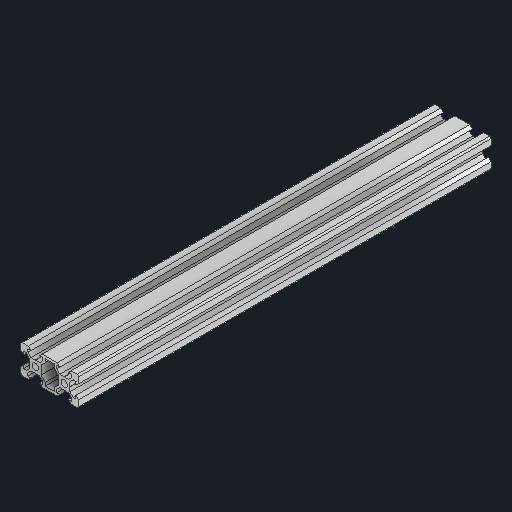
# Autodesk Inventor part: Perfil Estrutural em Alumínio 20x40 V-Slot - Canal 6 (286mm)
Saved by Autodesk Inventor 2026.1 (Build 301233000, 233)
## iProperties
Created: 2025-08-09
Part Number: Perfil Estrutural em Alumínio 20x40 V-Slot - Canal 6 (286mm)
Material: Alumínio 6061
Document SubType Name: Modeling
Designer: Cliente
Mass: 375 g
Surface Area: 849.316 cm^2
Volume: 84.4024 cm^3
Density: 2.5414 g/cm^3
Appearance: Alumínio - Polido
Author: Cliente
Autodesk Inventor part; units mm, degrees
ref_plane "YZ Plane" through (0, 0, 0) normal (1, 0, 0) x (0, 1, 0)
ref_plane "XZ Plane" through (0, 0, 0) normal (0, 1, 0) x (-1, 0, 0)
ref_plane "XY Plane" through (0, 0, 0) normal (0, 0, 1) x (1, 0, 0)
sketch "Esboço1" plane through (0, 0, 0) normal (0, 0, 1) x (1, 0, 0)
  line L0 (0, -10) -> (-19, -10)
  line L1 (-20, -9) -> (-20, 9)
  line L2 (-19, 10) -> (0, 10)
  line L3 (0, 10) -> (0, -10)
  line L4 (0, -10) -> (-20, 10) construction
  line L5 (-20, -10) -> (0, 10) construction
  circle A0 centre (-10, 0) radius 2.3
  line L6 (-6, -4) -> (-14, -4)
  line L7 (-14, -4) -> (-14, 4)
  line L8 (-14, 4) -> (-6, 4)
  line L9 (-6, 4) -> (-6, -4)
  line L10 (-6, -4) -> (-14, 4) construction
  line L11 (-14, -4) -> (-6, 4) construction
  line L12 (-13, 8.2) -> (-7, 8.2)
  line L13 (-13, 8.2) -> (-14.8, 10)
  line L14 (-13, 8.2) -> (-10.4544, 8.2) construction
  line L15 (-7, 8.2) -> (-5.2, 10)
  line L16 (-13, 4) -> (-7, 4)
  line L17 (-15.2, 8.2) -> (-15.2, 6.2)
  line L18 (-13, 4) -> (-15.2, 6.2)
  line L19 (-13, 4) -> (-9.8887, 4) construction
  line L20 (-13, 8.2) -> (-15.2, 8.2)
  line L21 (-7, 4) -> (-4.8, 6.2)
  line L22 (-4.8, 6.2) -> (-4.8, 8.2)
  line L23 (-4.8, 8.2) -> (-7, 8.2)
  line L24 (-18.2, -3) -> (-20, -4.8)
  line L25 (-18.2, -5.2) -> (-16.2, -5.2)
  line L26 (-18.2, -3) -> (-18.2, -5.2)
  line L27 (-18.2, 5.2) -> (-18.2, 3)
  line L28 (-18.2, 3) -> (-20, 4.8)
  line L29 (-14, -3) -> (-16.2, -5.2)
  line L30 (-14, 3) -> (-16.2, 5.2)
  line L31 (-16.2, 5.2) -> (-18.2, 5.2)
  line L32 (-7, -8.2) -> (-5.2, -10)
  line L33 (-4.8, -8.2) -> (-4.8, -6.2)
  line L34 (-7, -8.2) -> (-4.8, -8.2)
  line L35 (-15.2, -8.2) -> (-13, -8.2)
  line L36 (-13, -8.2) -> (-14.8, -10)
  line L37 (-7, -4) -> (-4.8, -6.2)
  line L38 (-13, -4) -> (-15.2, -6.2)
  line L39 (-15.2, -6.2) -> (-15.2, -8.2)
  circle A1 centre (-14, 0) radius 0.15
  circle A2 centre (-10, 4) radius 0.15
  circle A3 centre (-10, -4) radius 0.15
  line L40 (-6, -3) -> (-3.0998, -5.9002)
  line L41 (-3.0998, -5.9002) -> (-3.0998, -8.2)
  line L42 (-3.0998, -8.2) -> (0, -8.2)
  line L43 (-4.8, -6.2) -> (-3.0998, -5.9002)
  line L44 (-4.8, -6.2) -> (-3.0736, -6.2) construction
  line L45 (0, 0) -> (-2.6056, 0)
  line L46 (-6, 3) -> (-3.0998, 5.9002)
  line L47 (-3.0998, 5.9002) -> (-3.0998, 8.2)
  line L48 (-3.0998, 8.2) -> (0, 8.2)
  line L49 (0, -10) -> (19, -10)
  line L50 (20, -9) -> (20, 9)
  line L51 (19, 10) -> (0, 10)
  circle A4 centre (10, 0) radius 2.3
  line L52 (6, -4) -> (14, -4)
  line L53 (14, -4) -> (14, 4)
  line L54 (14, 4) -> (6, 4)
  line L55 (6, 4) -> (6, -4)
  line L56 (13, 8.2) -> (14.8, 10)
  line L57 (7, 8.2) -> (5.2, 10)
  line L58 (13, 4) -> (7, 4)
  line L59 (15.2, 8.2) -> (15.2, 6.2)
  line L60 (13, 4) -> (15.2, 6.2)
  line L61 (13, 4) -> (9.8887, 4) construction
  line L62 (13, 8.2) -> (15.2, 8.2)
  line L63 (7, 4) -> (4.8, 6.2)
  line L64 (4.8, 6.2) -> (4.8, 8.2)
  line L65 (4.8, 8.2) -> (7, 8.2)
  line L66 (18.2, -3) -> (20, -4.8)
  line L67 (18.2, -5.2) -> (16.2, -5.2)
  line L68 (18.2, -3) -> (18.2, -5.2)
  line L69 (18.2, 5.2) -> (18.2, 3)
  line L70 (18.2, 3) -> (20, 4.8)
  line L71 (14, -3) -> (16.2, -5.2)
  line L72 (14, 3) -> (16.2, 5.2)
  line L73 (16.2, 5.2) -> (18.2, 5.2)
  line L74 (7, -8.2) -> (5.2, -10)
  line L75 (4.8, -8.2) -> (4.8, -6.2)
  line L76 (7, -8.2) -> (4.8, -8.2)
  line L77 (15.2, -8.2) -> (13, -8.2)
  line L78 (13, -8.2) -> (14.8, -10)
  line L79 (7, -4) -> (4.8, -6.2)
  line L80 (13, -4) -> (15.2, -6.2)
  line L81 (15.2, -6.2) -> (15.2, -8.2)
  circle A5 centre (14, 0) radius 0.15
  circle A6 centre (10, 4) radius 0.15
  circle A7 centre (10, -4) radius 0.15
  line L82 (6, -3) -> (3.0998, -5.9002)
  line L83 (3.0998, -5.9002) -> (3.0998, -8.2)
  line L84 (3.0998, -8.2) -> (0, -8.2)
  line L85 (6, 3) -> (3.0998, 5.9002)
  line L86 (3.0998, 5.9002) -> (3.0998, 8.2)
  line L87 (3.0998, 8.2) -> (0, 8.2)
  arc A8 (-19, 10) -> (-20, 9) centre (-19, 9) ccw
  arc A9 (-20, -9) -> (-19, -10) centre (-19, -9) ccw
  arc A10 (20, 9) -> (19, 10) centre (19, 9) ccw
  arc A11 (19, -10) -> (20, -9) centre (19, -9) ccw
  point P0 (-10, 8.2)
  point P1 (20, 10)
  point P2 (20, -10)
  point P3 (-9.85, 4)
  point P4 (-10.15, 4)
  point P5 (-14, 0.15)
  point P6 (-14, -0.15)
  point P7 (-10.15, -4)
  point P8 (-9.85, -4)
  point P9 (9.85, -4)
  point P10 (10.15, -4)
  point P11 (14, -0.15)
  point P12 (14, 0.15)
  point P13 (10.15, 4)
  point P14 (9.85, 4)
  point P15 (-10.15, 4)
  point P16 (-9.85, 4)
  point P17 (10.15, 4)
  point P18 (9.85, 4)
  dimension "d0" = 20
  dimension "d1" = 20
  dimension "d2" = 4.6
  dimension "d3" = 8
  dimension "d4" = 6
  dimension "d5" = 1.8
  dimension "d6" = 135
  dimension "d7" = 135
  dimension "d9" = 6
  dimension "d10" = 2
  dimension "d11" = 135
  dimension "d12" = 2
  dimension "d13" = 135
  dimension "d16" = 180
  dimension "d18" = 0.3
  dimension "d19" = 0.3
  dimension "d20" = 0.3
  dimension "d21" = 10
  dimension "d24" = 1
  constraints: 186 end point, 53 symmetric about line, 22 point on line, 12 centre point, 10 midpoint, 8 horizontal, 8 point on circle, 8 tangent, 5 coincident, 5 parallel, 5 perpendicular, 3 equal length, 3 equal radius, 3 horizontal alignment, 2 vertical, 1 collinear, 1 vertical alignment, 41 other
  measures "d0" distance of L5.start L4.end
  measures "d1" distance of L4.end L2.end
  measures "d2" diameter of A0
  measures "d3" distance of L7.end L8.end
  measures "d4" distance of L12.start L12.end
  measures "d5" distance between parallel lines of L2 L12
  measures "d6" angle of L14 L13
  measures "d7" angle of L12 L15
  measures "d9" distance of L16.start L16.end
  measures "d10" distance of L17.end L17.start
  measures "d11" angle of L19 L18
  measures "d12" distance of L21.end L22.end
  measures "d13" angle of L8 L21
  measures "d18" diameter of A1
  measures "d19" diameter of A2
  measures "d20" diameter of A3
  measures "d21" angle of L44 L43
  measures "d24" radius of A8
extrude "Extrusão1" add sketch "Esboço1" along normal mid plane 286 contours L0 L32 L34 L33 L43 L41 L42 L3 | L3 L84 L83 L82 L55 L52 L79 L75 L76 L74 L49 | L0 A9 L1 L24 L26 L25 L29 L7 L6 L38 L39 L35 L36 | L78 L77 L81 L80 L52 L53 L71 L67 L68 L66 L50 A11 L49 | L48 L47 L46 L9 L8 L21 L22 L23 L15 L2 L3 | L3 L51 L57 L65 L64 L63 L54 L55 L85 L86 L87 | L43 L37 L6 L9 L40 | L9 L6 A3 L7 A1 L8 A2 | L55 L54 A6 L53 A5 L52 A7 | L1 A8 L2 L13 L20 L17 L18 L8 L7 L30 L31 L27 L28 | L51 A10 L50 L70 L69 L73 L72 L53 L54 L60 L59 L62 L56
